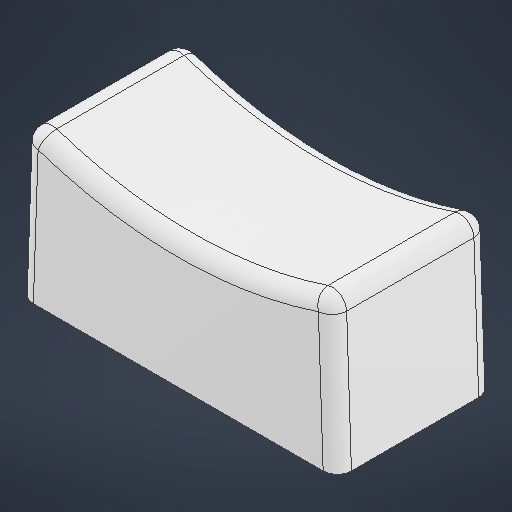
# Autodesk Inventor part: Potikan nuppi
Saved by Autodesk Inventor 2026.1 (Build 301233020, 233B)
## iProperties
Created: 2025-11-03
Part Number: Potikan nuppi
Material: ABS Plastic
Document SubType Name: Modeling
Designer: kuuse
Density: 1.06 g/cm^3
Appearance: Smooth - White
Author: kuuse
Autodesk Inventor part; units mm, degrees
ref_plane "YZ Plane" through (0, 0, 0) normal (1, 0, 0) x (0, 1, 0)
ref_plane "XZ Plane" through (0, 0, 0) normal (0, 1, 0) x (-1, 0, 0)
ref_plane "XY Plane" through (0, 0, 0) normal (0, 0, 1) x (1, 0, 0)
sketch "Sketch1" plane through (0, 0, 0) normal (0, 0, 1) x (1, 0, 0)
  line L0 (11.25, 0) -> (-11.25, 0)
  line L1 (-11.25, 0) -> (-10.8659, 11)
  arc A0 (-10.8659, 11) -> (10.8659, 11) centre (0, 38.9631) ccw
  line L2 (10.8659, 11) -> (11.25, 0)
  line L3 (10.8659, 11) -> (-10.8659, 11) construction
  line L4 (2.1, 0) -> (2.1, 8)
  line L5 (2.1, 8) -> (-2.1, 8)
  line L6 (-2.1, 8) -> (-2.1, 0)
  line L7 (0, 0) -> (0, 8) construction
  dimension "d0" = 22.5
  dimension "d1" = 88
  dimension "d2" = 88
  dimension "d3" = 11
  dimension "d4" = 30
  dimension "d5" = 4.2
  dimension "d6" = 8
  constraints: 16 end point, 3 perpendicular, 2 horizontal, 2 midpoint, 2 point on circle, 2 point on line, 1 centre point, 1 coincident, 1 vertical
  measures "d0" distance of L0.start L0.end
  measures "d1" angle of L2 L0
  measures "d2" angle of L1 L0
  measures "d3" distance between parallel lines of L0 L3
  measures "d4" radius of A0
  measures "d5" distance of L4.end L5.end
  measures "d6" distance between parallel lines of L5 L0
extrude "Extrusion1" add sketch "Sketch1" along normal mid plane 11
extrude "Extrusion2" cut sketch "Sketch1" along normal mid plane 1.2 contours L0 L6 L5 L4
fillet "Fillet1" radius 1 8 edges at (-10.8659, 11, 0) (0, 8.9631, -5.5) (0, 8.9631, 5.5) (10.8659, 11, 0) (11.0579, 5.5, 5.5) (11.0579, 5.5, -5.5) (-11.0579, 5.5, 5.5) (-11.0579, 5.5, -5.5)
equation "\"d2\" = d1"
body "Solid1"
